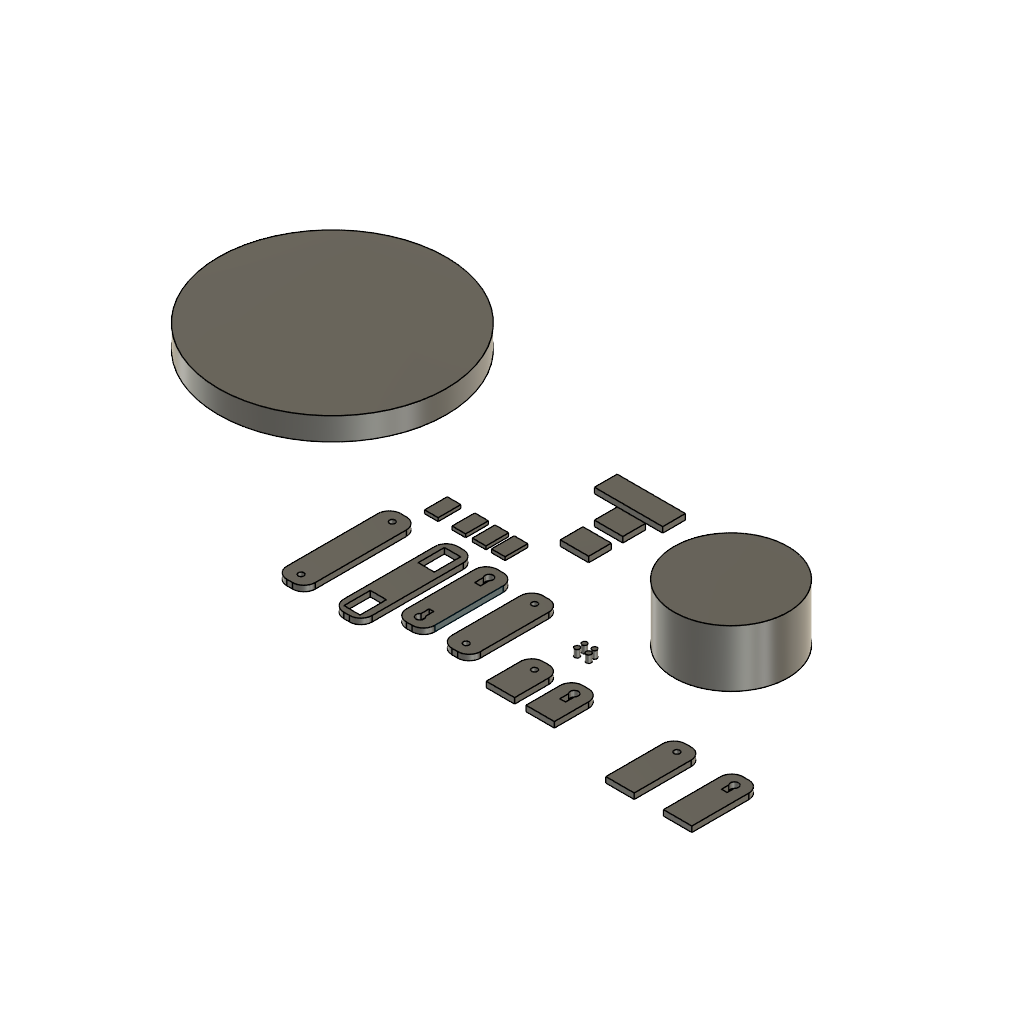
Robotska ruka 1 (Autodesk Fusion 360 design; units mm, degrees)
part number: 2026-10-18-17-55-23-177
Autodesk Fusion 360 part; units mm, degrees
sketch "Sketch1" plane through (0, 0, 0) normal (0, 0, 1) x (1, 0, 0)
  line L0 (-30, -50) -> (-50, -50)
  line L1 (-40, 50) -> (-35, 50)
  line L2 (-25, 40) -> (-25, -40)
  line L3 (-35, -50) -> (-40, -50)
  line L4 (-50, -40) -> (-50, 40)
  line L5 (-5, 50) -> (0, 50)
  line L6 (10, 40) -> (10, -20)
  line L7 (0, -30) -> (-5, -30)
  line L8 (-15, -20) -> (-15, 40)
  circle A0 centre (150, 50) radius 40
  arc A1 (-40, 50) -> (-50, 40) centre (-40, 40) ccw
  arc A2 (-25, 40) -> (-35, 50) centre (-35, 40) ccw
  arc A3 (-35, -50) -> (-25, -40) centre (-35, -40) ccw
  arc A4 (-50, -40) -> (-40, -50) centre (-40, -40) ccw
  arc A5 (0, -30) -> (10, -20) centre (0, -20) ccw
  arc A6 (-15, -20) -> (-5, -30) centre (-5, -20) ccw
  arc A7 (-5, 50) -> (-15, 40) centre (-5, 40) ccw
  arc A8 (10, 40) -> (0, 50) centre (0, 40) ccw
  line L9 (23.7513, 80.2133) -> (37.909, 80.2133)
  line L10 (37.909, 80.2133) -> (37.909, 57.1492)
  line L11 (37.909, 57.1492) -> (23.7513, 57.1492)
  line L12 (23.7513, 57.1492) -> (23.7513, 80.2133)
  line L13 (-44.8918, -21.8497) -> (-30.7341, -21.8497)
  line L14 (-30.7341, -21.8497) -> (-30.7341, -44.9138)
  line L15 (-44.8918, -44.9138) -> (-44.8918, -21.8497)
  line L16 (-30.7341, -44.9138) -> (-44.8918, -44.9138)
  line L17 (-44.9584, 20.2996) -> (-44.9584, 43.3637)
  line L18 (-44.9584, 43.3637) -> (-30.8008, 43.3637)
  line L19 (-30.8008, 43.3637) -> (-30.8008, 20.2996)
  line L20 (-30.8008, 20.2996) -> (-44.9584, 20.2996)
  line L21 (-90, 50) -> (-85, 50)
  line L22 (-75, 40) -> (-75, -40)
  line L23 (-85, -50) -> (-90, -50)
  line L24 (-100, -40) -> (-100, 40)
  arc A9 (-90, 50) -> (-100, 40) centre (-90, 40) ccw
  arc A10 (-75, 40) -> (-85, 50) centre (-85, 40) ccw
  arc A11 (-85, -50) -> (-75, -40) centre (-85, -40) ccw
  arc A12 (-100, -40) -> (-90, -50) centre (-90, -40) ccw
  circle A13 centre (-87.5, -40) radius 2.5
  circle A14 centre (-87.471, 40) radius 2.5
  circle A15 centre (-3, -20) radius 3.5
  line L25 (-5, -10) -> (-1, -10)
  line L26 (-1, -10) -> (-1, -20)
  line L27 (-1, -20) -> (-5, -20)
  line L28 (-5, -20) -> (-5, -10)
  circle A16 centre (-2.5471, 40.1322) radius 3.5
  line L29 (-5, 40) -> (0, 40)
  line L30 (0, 40) -> (0, 30)
  line L31 (0, 30) -> (-5, 30)
  line L32 (-5, 30) -> (-5, 40)
  line L33 (35, 50) -> (40, 50)
  line L34 (50, 40) -> (50, -20)
  line L35 (40, -30) -> (35, -30)
  line L36 (25, -20) -> (25, 40)
  arc A17 (35, 50) -> (25, 40) centre (35, 40) ccw
  arc A18 (50, 40) -> (40, 50) centre (40, 40) ccw
  arc A19 (40, -30) -> (50, -20) centre (40, -20) ccw
  arc A20 (25, -20) -> (35, -30) centre (35, -20) ccw
  circle A21 centre (37.5, -20) radius 2.5
  circle A22 centre (37.5, 40) radius 2.5047
  line L37 (85, 0) -> (90, 0)
  line L38 (100, -10) -> (100, -40)
  line L39 (100, -40) -> (75, -40)
  line L40 (75, -40) -> (75, -10)
  line L41 (135.67, -40.7644) -> (110.67, -40.7644)
  line L42 (135.67, -10.7644) -> (135.67, -40.7644)
  line L43 (120.67, -0.7644) -> (125.67, -0.7644)
  line L44 (110.67, -40.7644) -> (110.67, -10.7644)
  arc A23 (85, 0) -> (75, -10) centre (85, -10) ccw
  arc A24 (100, -10) -> (90, 0) centre (90, -10) ccw
  arc A25 (135.67, -10.7644) -> (125.67, -0.7644) centre (125.67, -10.7644) ccw
  arc A26 (120.67, -0.7644) -> (110.67, -10.7644) centre (120.67, -10.7644) ccw
  circle A27 centre (87.5, -10) radius 2.5
  circle A28 centre (123.1892, -10.7644) radius 3.5
  line L45 (120.67, -10.7644) -> (125.67, -10.7644)
  line L46 (125.67, -10.7644) -> (125.67, -20.9867)
  line L47 (125.67, -20.9867) -> (120.67, -20.9867)
  line L48 (120.67, -20.9867) -> (120.67, -10.7644)
  line L49 (210, 0) -> (215, 0)
  line L50 (225, -10) -> (225, -60)
  line L51 (225, -60) -> (200, -60)
  line L52 (200, -60) -> (200, -10)
  line L53 (260.4035, 0.186) -> (265.4035, 0.186)
  line L54 (275.4035, -59.814) -> (250.4035, -59.814)
  line L55 (275.4035, -9.814) -> (275.4035, -59.814)
  line L56 (250.4035, -59.814) -> (250.4035, -9.814)
  arc A29 (210, 0) -> (200, -10) centre (210, -10) ccw
  arc A30 (225, -10) -> (215, 0) centre (215, -10) ccw
  arc A31 (260.4035, 0.186) -> (250.4035, -9.814) centre (260.4035, -9.814) ccw
  arc A32 (275.4035, -9.814) -> (265.4035, 0.186) centre (265.4035, -9.814) ccw
  circle A33 centre (212.5, -10) radius 2.5
  circle A34 centre (263, -10) radius 3.5
  line L57 (260.4035, -9.814) -> (265.4035, -9.814)
  line L58 (265.4035, -9.814) -> (265.4035, -18.814)
  line L59 (265.4035, -18.814) -> (260.4035, -18.814)
  line L60 (260.4035, -18.814) -> (260.4035, -9.814)
  dimension "d1" = 10
  dimension "d2" = 10
  dimension "d3" = 5
  dimension "d4" = 5
  dimension "d5" = 7
  dimension "d6" = 7
  dimension "d7" = 10
  dimension "d8" = 10
  dimension "d9" = 7
  dimension "d10" = 10
  dimension "d11" = 7
  dimension "d12" = 9
  dimension "d13" = 5
  constraint horizontal L0
  constraint horizontal L1
  constraint vertical L2
  constraint horizontal L3
  constraint vertical L4
  constraint horizontal L5
  constraint vertical L6
  constraint horizontal L7
  constraint vertical L8
  constraint tangent L1 A1
  constraint tangent L4 A1
  constraint tangent L1 A2
  constraint tangent L2 A2
  constraint equal A1 A2
  constraint tangent L2 A3
  constraint tangent L3 A3
  constraint equal A1 A3
  constraint tangent L3 A4
  constraint tangent L4 A4
  constraint equal A1 A4
  constraint tangent L6 A5
  constraint tangent L7 A5
  constraint equal A1 A5
  constraint tangent L7 A6
  constraint tangent L8 A6
  constraint equal A1 A6
  constraint tangent L5 A7
  constraint tangent L8 A7
  constraint equal A1 A7
  constraint tangent L5 A8
  constraint tangent L6 A8
  constraint equal A1 A8
  constraint horizontal L9
  constraint vertical L10
  constraint horizontal L11
  constraint vertical L12
  constraint horizontal L13
  constraint vertical L14
  constraint horizontal L16
  constraint vertical L15
  constraint horizontal L18
  constraint vertical L19
  constraint horizontal L20
  constraint vertical L17
  constraint horizontal L21
  constraint vertical L22
  constraint horizontal L23
  constraint vertical L24
  constraint tangent L21 A9
  constraint tangent L24 A9
  constraint tangent L21 A10
  constraint tangent L22 A10
  constraint equal A9 A10
  constraint tangent L22 A11
  constraint tangent L23 A11
  constraint equal A9 A11
  constraint tangent L23 A12
  constraint tangent L24 A12
  constraint equal A9 A12
  constraint coincident A12.centre A13
  constraint horizontal L25
  constraint vertical L26
  constraint horizontal L27
  constraint vertical L28
  constraint horizontal L29
  constraint vertical L30
  constraint horizontal L31
  constraint vertical L32
  constraint coincident A7.centre L29.start
  constraint horizontal L33
  constraint vertical L34
  constraint horizontal L35
  constraint vertical L36
  constraint tangent L33 A17
  constraint tangent L36 A17
  constraint tangent L33 A18
  constraint tangent L34 A18
  constraint equal A17 A18
  constraint tangent L34 A19
  constraint tangent L35 A19
  constraint equal A17 A19
  constraint tangent L35 A20
  constraint tangent L36 A20
  constraint equal A17 A20
  constraint horizontal L37
  constraint vertical L38
  constraint horizontal L39
  constraint vertical L40
  constraint horizontal L43
  constraint vertical L42
  constraint horizontal L41
  constraint vertical L44
  constraint tangent L37 A23
  constraint tangent L40 A23
  constraint tangent L37 A24
  constraint tangent L38 A24
  constraint equal A23 A24
  constraint tangent L42 A25
  constraint tangent L43 A25
  constraint equal A23 A25
  constraint tangent L43 A26
  constraint tangent L44 A26
  constraint equal A23 A26
  constraint coincident A23.centre A27
  constraint horizontal L45
  constraint vertical L46
  constraint horizontal L47
  constraint vertical L48
  constraint coincident A26.centre L45.start
  constraint horizontal L49
  constraint vertical L50
  constraint horizontal L51
  constraint vertical L52
  constraint horizontal L53
  constraint vertical L55
  constraint horizontal L54
  constraint vertical L56
  constraint tangent L49 A29
  constraint tangent L52 A29
  constraint tangent L49 A30
  constraint tangent L50 A30
  constraint equal A29 A30
  constraint tangent L53 A31
  constraint tangent L56 A31
  constraint equal A29 A31
  constraint tangent L53 A32
  constraint tangent L55 A32
  constraint equal A29 A32
  constraint coincident A29.centre A33
  constraint horizontal L57
  constraint vertical L58
  constraint horizontal L59
  constraint vertical L60
  constraint coincident A31.centre L57.start
  measures "d1" radius of A1
  measures "d2" radius of A9
  measures "d3" diameter of A13
  measures "d4" diameter of A14
  measures "d5" diameter of A15
  measures "d6" diameter of A16
  measures "d7" radius of A17
  measures "d8" radius of A23
  measures "d9" diameter of A28
  measures "d10" radius of A29 L0.end
  measures "d11" diameter of A34
  measures "d12" distance of A31.centre L59.end
  measures "d13" distance of A31.centre A32.centre
extrude "Extrude1" add sketch "Sketch1" along normal blind 5 contours L0 L1 L2 L3 L4 A1 A2 A3 A4 | L5 L6 L7 L8 A5 A6 A7 A8 | L21 L22 L23 L24 A9 A10 A11 A12 | L33 L34 L35 L36 A17 A18 A19 A20 | L37 L38 L39 L40 A23 A24 | L41 L42 L43 L44 A25 A26 | L49 L50 L51 L52 A29 A30 | L53 L54 L55 L56 A31 A32 makes body 1 at (122.3367, -34.1718, 0) makes body 2 at (-40.217, 6.2498, 0) makes body 3 at (6.6667, 16.6667, 0) makes body 4 at (212.4377, -44.1643, 0) makes body 5 at (87.4377, -30.831, 0) makes body 6 at (-96.1378, -12.5576, 0) makes body 7 at (28.8616, 19.2228, 0) makes body 8 at (262.0702, -46.1473, 5)
sketch "Sketch2" plane through (10, 0, 0) normal (1, 0, 0) x (0, 1, 0)
  line L0 (-20, 0) -> (40, 0)
  line L1 (40, 0) -> (40, 5)
  line L2 (40, 5) -> (-20, 5)
  line L3 (-20, 5) -> (-20, 0)
sketch "Sketch3" plane through (0, 0, 0) normal (0, 0, 1) x (1, 0, 0)
  circle A0 centre (150, 100) radius 50
extrude "Extrude2" add sketch "Sketch3" along normal blind 50 separate body makes body 9
sketch "Sketch4" plane through (0, 0, 0) normal (0, 0, 1) x (1, 0, 0)
  line L0 (-60, 85) -> (-48, 85)
  line L1 (-48, 85) -> (-48, 65)
  line L2 (-48, 65) -> (-60, 65)
  line L3 (-60, 65) -> (-60, 85)
  line L4 (-29.9352, 64.7633) -> (-41.9352, 64.7633)
  line L5 (-41.9352, 84.7633) -> (-29.9352, 84.7633)
  line L6 (-29.9352, 84.7633) -> (-29.9352, 64.7633)
  line L7 (-41.9352, 64.7633) -> (-41.9352, 84.7633)
  line L8 (-72.3756, 65.2367) -> (-84.3756, 65.2367)
  line L9 (-84.3756, 85.2367) -> (-72.3756, 85.2367)
  line L10 (-72.3756, 85.2367) -> (-72.3756, 65.2367)
  line L11 (-84.3756, 65.2367) -> (-84.3756, 85.2367)
  line L12 (-13.2903, 64.9211) -> (-25.2903, 64.9211)
  line L13 (-25.2903, 84.9211) -> (-13.2903, 84.9211)
  line L14 (-13.2903, 84.9211) -> (-13.2903, 64.9211)
  line L15 (-25.2903, 64.9211) -> (-25.2903, 84.9211)
  constraint horizontal L0
  constraint vertical L1
  constraint horizontal L2
  constraint vertical L3
  constraint horizontal L5
  constraint vertical L6
  constraint horizontal L4
  constraint vertical L7
  constraint horizontal L9
  constraint vertical L10
  constraint horizontal L8
  constraint vertical L11
  constraint horizontal L13
  constraint vertical L14
  constraint horizontal L12
  constraint vertical L15
extrude "Extrude3" add sketch "Sketch4" along normal blind 3 separate body makes body 10 at (-56, 78.3333, 0) makes body 11 at (-33.9352, 71.43, 0) makes body 12 at (-76.3756, 71.9033, 0) makes body 13 at (-17.2903, 78.2544, 0)
sketch "Sketch5" plane through (0, 0, 0) normal (0, 0, 1) x (1, 0, 0)
  circle A0 centre (100, 25) radius 2.281
  line L0 (-48, 65) -> (-60, 65)
  line L1 (-60, 85) -> (-48, 85)
  line L2 (-48, 85) -> (-48, 65)
  line L3 (-60, 65) -> (-60, 85)
  circle A1 centre (90.9428, 30.4343) radius 2.281
  circle A2 centre (99.3479, 30.8691) radius 2.281
  circle A3 centre (90.7978, 24.058) radius 2.281
  constraint horizontal L1
  constraint vertical L2
  constraint horizontal L0
  constraint vertical L3
extrude "Extrude4" add sketch "Sketch5" along normal blind 6.5 separate body contours A0 | A1 | A2 | A3 makes body 14 at (99.6315, 33.1324, 4.3333) makes body 15 at (91.0815, 26.3213, 4.3333) makes body 16 at (91.2264, 32.6976, 4.3333) makes body 17 at (100.2836, 27.2633, 4.3333)
sketch "Sketch6" plane through (0, 0, 0) normal (0, 0, 1) x (1, 0, 0)
  line L0 (0, 150) -> (25, 150)
  line L1 (25, 150) -> (25, 130)
  line L2 (25, 130) -> (0, 130)
  line L3 (0, 130) -> (0, 150)
  line L4 (-25, 175) -> (35, 175)
  line L5 (35, 175) -> (35, 155)
  line L6 (35, 155) -> (-25, 155)
  line L7 (-25, 155) -> (-25, 175)
  constraint horizontal L0
  constraint vertical L1
  constraint horizontal L2
  constraint vertical L3
  constraint horizontal L4
  constraint vertical L5
  constraint horizontal L6
  constraint vertical L7
extrude "Extrude5" add sketch "Sketch6" along normal blind 5 separate body makes body 18 at (-5, 168.3333, 0) makes body 19 at (8.3333, 143.3333, 0)
sketch "Sketch7" plane through (0, 0, 0) normal (0, 0, 1) x (1, 0, 0)
  line L0 (0, 120) -> (25, 120)
  line L1 (25, 120) -> (25, 100)
  line L2 (25, 100) -> (0, 100)
  line L3 (0, 100) -> (0, 120)
  constraint horizontal L0
  constraint vertical L1
  constraint horizontal L2
  constraint vertical L3
extrude "Extrude6" add sketch "Sketch7" along normal blind 5 separate body makes body 20
sketch "Sketch8" plane through (0, 0, 50) normal (0, 0, 1) x (-1, 0, 0)
  circle A0 centre (-150, -100) radius 50
  circle A1 centre (200, -100) radius 100
extrude "Extrude7" add sketch "Sketch8" along normal blind 20 separate body contours A1 makes body 21
